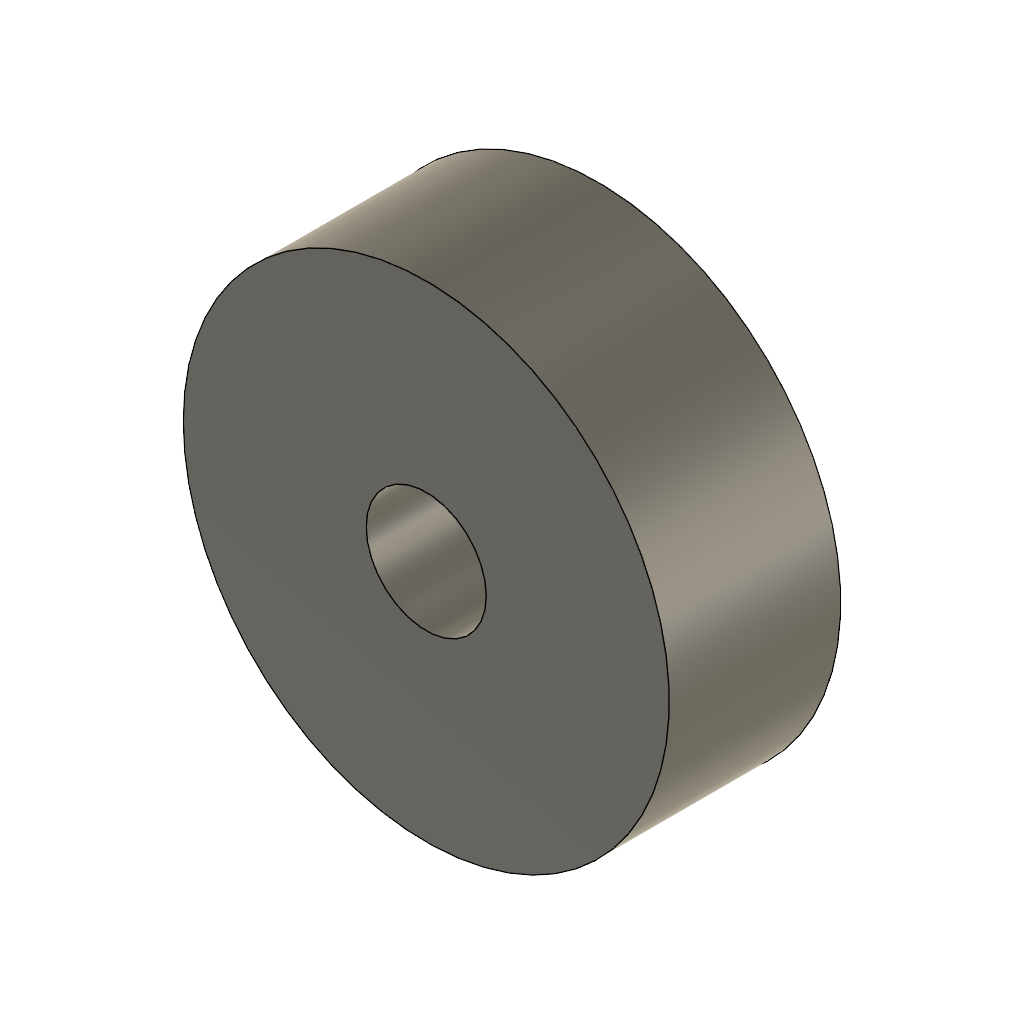
WheelType2 (Autodesk Fusion 360 design; units mm, degrees)
part number: 2026-10-04-14-52-17-091
Autodesk Fusion 360 part; units mm, degrees
sketch "Szkic1" plane through (0, 0, 0) normal (0, 1, 0) x (1, 0, 0)
  circle A0 centre (0, 0) radius 2.1
  circle A1 centre (0, 0) radius 8.5
  dimension "d7" = 4.2
  dimension "d10" = 17
  measures "d7" diameter of A0
  measures "d10" diameter of A1
extrude "Wyciągnięcie proste1" add sketch "Szkic1" along normal blind 6
